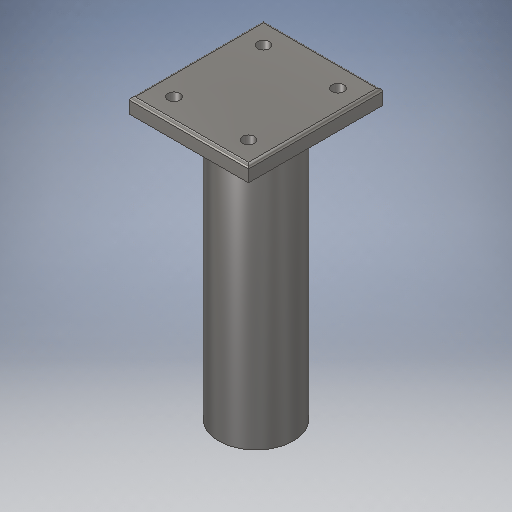
# Autodesk Inventor part: BT009_bensen22_26
Saved by Autodesk Inventor 2025.3 (Build 293356000, 356)
## iProperties
Company: HTBLA Kaindorf
RuleStatus: InUse
Created: 2026-08-10
Part Number: BT009_bensen22_26
Project: Biegeroboter
Material: Stahl, Legierung
Description: verlängerung_bolzen_v1
Document SubType Name: Modeling
Designer: bensen22
Density: 7.73 g/cm^3
Appearance: Halbpoliert
Mass: 408.849 g
Surface Area: 115.958 cm^2
Volume: 52.8912 cm^3
AfterDocNew0: iProperties-Editor_aufrufen
Author: sebas
Keywords: 2026
Comments: Werkstoff 100Cr6, gehaertet 58-62 HRC, Laufflaeche Nadelhuelse HK2520 geschliffen, D25 h6. Laenge 90 mm (vorher 80 mm, Aenderung 08.10.2026).
Autodesk Inventor part; units mm, degrees
ref_plane "YZ Plane" through (0, 0, 0) normal (1, 0, 0) x (0, 1, 0)
ref_plane "XZ Plane" through (0, 0, 0) normal (0, 1, 0) x (-1, 0, 0)
ref_plane "XY Plane" through (0, 0, 0) normal (0, 0, 1) x (1, 0, 0)
sketch "Skizze3" plane through (0, 0, 0) normal (0, 0, 1) x (1, 0, 0)
  line L0 (-22.5, 20) -> (22.5, 20)
  line L1 (22.5, 20) -> (22.5, -20)
  line L2 (22.5, -20) -> (-22.5, -20)
  line L3 (-22.5, -20) -> (-22.5, 20)
  line L4 (0, -28) -> (0, 28) projected
  line L5 (-31.5, 0) -> (31.5, 0) projected
  circle A0 centre (0, 0) radius 12.5
  point P0 (-15, 12.5)
  point P1 (15, 12.5)
  point P2 (15, -12.5)
  point P3 (-15, -12.5)
  dimension "d4" = 40
  dimension "d5" = 45
  dimension "d6" = 30
  dimension "d7" = 25
  dimension "d17" = 25
  constraints: 8 end point, 4 symmetric about line, 2 parallel, 1 centre point, 1 coincident, 1 horizontal, 1 perpendicular, 2 other
  measures "d4" distance between parallel lines of L2 L0
  measures "d5" distance between parallel lines of L3 L1
  measures "d6" distance of point (15, 12.5) point (-15, 12.5)
  measures "d7" distance of point (-15, -12.5) point (-15, 12.5)
  measures "d17" diameter of A0
extrude "Extrusion3" add sketch "Skizze3" along normal blind 5
hole "Bohrung1" at (-15, 12.5, 0) at (15, 12.5, 0) at (15, -12.5, 0) at (-15, -12.5, 0) direction (0, 0, 1) diameter 4 depth 5
extrude "Extrusion4" add sketch "Skizze3" against normal blind 90 contours A0 L5 L4 | L4 L5 A0 | L5 L4 A0 | L5 A0 L4
fillet "Rundung1" radius 1 4 edges at (22.5, 0, 5) (0, -20, 5) (-22.5, 0, 5) (0, 20, 5)
